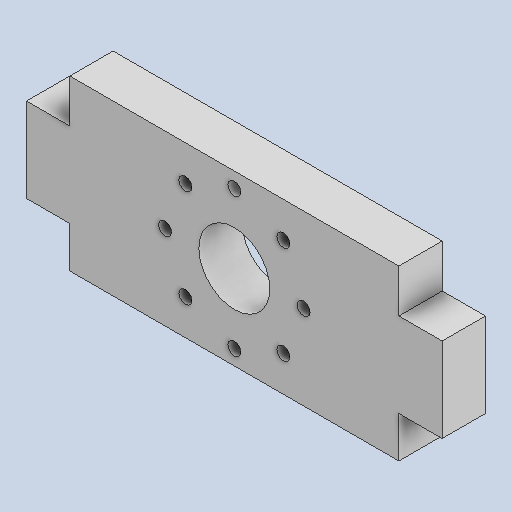
# Autodesk Inventor part: ElbowTop
Saved by Autodesk Inventor 2025.2 (Build 292293000, 293)
## iProperties
Created: 2025-06-27
Part Number: ElbowTop
Material: Generic
Document SubType Name: Modeling
Designer: ricoa
Density: 1 g/cm^3
Appearance: Default
Author: ricoa
Autodesk Inventor part; units mm, degrees
ref_plane "YZ Plane" through (0, 0, 0) normal (1, 0, 0) x (0, 1, 0)
ref_plane "XZ Plane" through (0, 0, 0) normal (0, 1, 0) x (-1, 0, 0)
ref_plane "XY Plane" through (0, 0, 0) normal (0, 0, 1) x (1, 0, 0)
sketch "Sketch1" plane through (0, 0, 0) normal (0, 0, 1) x (1, 0, 0)
  circle A0 centre (0, 0) radius 4 projected
  circle A1 centre (-5.6569, 5.6569) radius 0.75 projected
  circle A2 centre (-8, 0) radius 0.75 projected
  circle A3 centre (-5.6569, -5.6569) radius 0.75 projected
  circle A4 centre (0, -8) radius 0.75 projected
  circle A5 centre (5.6569, -5.6569) radius 0.75 projected
  circle A6 centre (8, 0) radius 0.75 projected
  circle A7 centre (5.6569, 5.6569) radius 0.75 projected
  circle A8 centre (0, 8) radius 0.75 projected
  circle A9 centre (0, 0) radius 4.1
  line L0 (0, 0) -> (19, 0) construction
  line L1 (0, 9.75) -> (19, 9.75)
  line L2 (19, 9.75) -> (19, 4.75)
  line L3 (19, 4.75) -> (24, 4.75)
  line L4 (24, 4.75) -> (24, 0)
  line L5 (24, 0) -> (24, -5)
  line L6 (24, -5) -> (19, -5)
  line L7 (19, -5) -> (19, -9.75)
  line L8 (19, -9.75) -> (0, -9.75)
  line L9 (0, 9.75) -> (0, -9.75) construction
  line L10 (0, 0) -> (-19, 0) construction
  line L11 (0, 9.75) -> (-19, 9.75)
  line L12 (-19, 9.75) -> (-19, 4.75)
  line L13 (-19, 4.75) -> (-24, 4.75)
  line L14 (-24, 4.75) -> (-24, 0)
  line L15 (-24, 0) -> (-24, -5)
  line L16 (-24, -5) -> (-19, -5)
  line L17 (-19, -5) -> (-19, -9.75)
  line L18 (-19, -9.75) -> (0, -9.75)
  point P0 (0, 0)
  point P1 (-5.6569, -5.6569)
  point P2 (-8, 0)
  point P3 (-5.6569, 5.6569)
  dimension "d0" = 8.2
  dimension "d1" = 19
  dimension "d2" = 5
  dimension "d3" = 5
  dimension "d4" = 5
  constraints: 38 end point, 11 symmetric about line, 6 point on line, 4 perpendicular, 2 coincident, 2 horizontal, 1 centre point, 1 vertical
  measures "d0" diameter of A9
  measures "d1" distance of L0.start L0.end
  measures "d2" distance of L1.end L2.end
  measures "d3" distance of L2.end L3.end
  measures "d4" distance of L4.end L5.end
extrude "Extrusion1" add sketch "Sketch1" along normal blind 5 contours L1 L2 L3 L4 L5 L6 L7 L8 L18 L17 L16 L15 L14 L13 L12 L11
body "Solid1"
